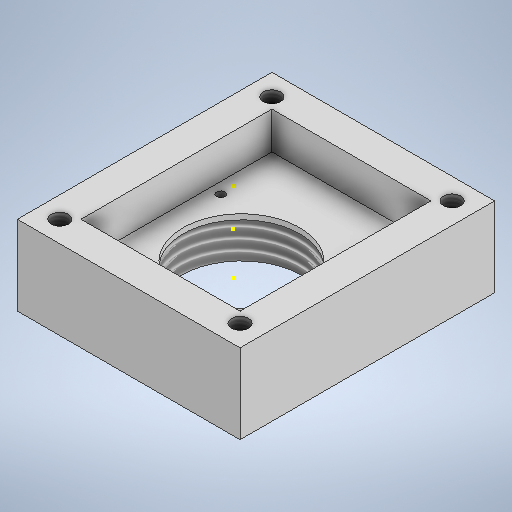
# Autodesk Inventor part: front holder
Saved by Autodesk Inventor 2025 (Build 290162010, 162A)
## iProperties
Created: 2025-05-06
Part Number: front holder
Material: Generisch
Document SubType Name: Sheet Metal
Designer: sharmalakshya
Density: 1 g/cm^3
Sheet Metal Rule: Default
Appearance: Vorgabe
Author: sharmalakshya
Autodesk Inventor part; units mm, degrees
ref_plane "YZ Plane" through (0, 0, 0) normal (1, 0, 0) x (0, 1, 0)
ref_plane "XZ Plane" through (0, 0, 0) normal (0, 1, 0) x (-1, 0, 0)
ref_plane "XY Plane" through (0, 0, 0) normal (0, 0, 1) x (1, 0, 0)
sketch "Sketch1" plane through (0, 0, 0) normal (0, 1, 0) x (-1, 0, 0)
  line L0 (14.8437, 25.7748) -> (-27.1563, 25.7748)
  line L1 (-27.1563, 25.7748) -> (-27.1563, -22.2252)
  line L2 (-27.1563, -22.2252) -> (14.8437, -22.2252)
  line L3 (14.8437, -22.2252) -> (14.8437, 25.7748)
  point P0 (0, 0)
  dimension "d0" = 48
  dimension "d1" = 42
  constraints: 8 end point, 2 parallel, 1 horizontal, 1 perpendicular
  measures "d0" distance of L2.end L0.start
  measures "d1" distance of L1.end L2.end
extrude "Extrusion1" add sketch "Sketch1" along normal blind 15
sketch "Sketch2" plane through (0, 15, 0) normal (0, 1, 0) x (1, 0, 0)
  line L0 (-8.8437, -19.7748) -> (21.1563, -19.7748)
  line L1 (21.1563, -19.7748) -> (21.1563, 16.2252)
  line L2 (21.1563, 16.2252) -> (-8.8437, 16.2252)
  line L3 (-8.8437, 16.2252) -> (-8.8437, -19.7748)
  line L4 (-14.8437, 22.2252) -> (-14.8437, -25.7748) projected
  line L5 (27.1563, 22.2252) -> (-14.8437, 22.2252) projected
  point P0 (0, 0)
  dimension "d4" = 36
  dimension "d5" = 30
  dimension "d6" = 6
  dimension "d7" = 6
  constraints: 8 end point, 2 parallel, 1 horizontal, 1 perpendicular
  measures "d4" distance of L2.end L0.start
  measures "d5" distance of L1.end L2.end
  measures "d6" distance between parallel lines of L4 L3
  measures "d7" distance between parallel lines of L5 L2
extrude "Extrusion2" cut sketch "Sketch2" against normal blind 7
sketch "Sketch4" plane through (0, 8, 0) normal (0, 1, 0) x (1, 0, 0)
  point P0 (0, 0)
sketch "Sketch6" plane through (0, 8, 0) normal (0, 1, 0) x (1, 0, 0)
  point P0 (0, 0)
sketch "Sketch7" plane through (0, 8, 0) normal (0, 1, 0) x (1, 0, 0)
  line L0 (21.1563, -19.7748) -> (-8.8437, -19.7748) projected
  line L1 (21.1563, -19.7748) -> (17.7563, -19.7748)
  line L2 (17.7563, -19.7748) -> (17.7563, -16.0248)
  line L3 (17.7563, -16.0248) -> (21.1563, -16.0248)
  line L4 (21.1563, -16.0248) -> (21.1563, -19.7748)
  line L5 (17.7563, -16.0248) -> (-6.7437, -16.0248)
  line L6 (-6.7437, -16.0248) -> (-6.7437, 4.4752)
  line L7 (-6.7437, 4.4752) -> (17.7563, 4.4752)
  line L8 (17.7563, 4.4752) -> (17.7563, -16.0248)
  point P0 (0, 0)
  dimension "d31" = 3.75
  dimension "d32" = 3.4
  dimension "d33" = 24.5
  dimension "d34" = 20.5
  constraints: 16 end point, 4 parallel, 2 horizontal, 2 perpendicular
  measures "d31" distance of L1.end L2.end
  measures "d32" distance of L2.end L3.end
  measures "d33" distance of L2.end L5.end
  measures "d34" distance of L7.end L2.end
hole "Hole3" at (17.7563, 8, 16.0248) at (-6.7437, 8, -4.4752) direction (0, -1, 0) diameter 1.567 depth 6.2992 thread size "M2x0.4" class "6H" standard "ANSI Metric M Profile"
sketch "Sketch8" plane through (0, 0, 0) normal (0, -1, 0) x (1, 0, 0)
  point P0 (0, 0)
sketch "Sketch9" plane through (0, 0, 0) normal (0, -1, 0) x (1, 0, 0)
  line L0 (-14.8437, -22.2252) -> (-14.8437, 25.7748) projected
  line L1 (-14.8437, 25.7748) -> (6.1563, 25.7748)
  line L2 (6.1563, 25.7748) -> (6.1563, 4.5248)
  line L3 (6.1563, 4.5248) -> (-14.8437, 4.5248)
  line L4 (-14.8437, 4.5248) -> (-14.8437, 25.7748)
  point P0 (0, 0)
  dimension "d42" = 21.25
  dimension "d43" = 21
  constraints: 8 end point, 2 parallel, 1 horizontal, 1 perpendicular
  measures "d42" distance of L1.end L2.end
  measures "d43" distance of L2.end L3.end
hole "Hole4" at (6.1563, 0, 4.5248) direction (0, 1, 0) diameter 22.8349 depth 7 thread size "M25x2" class "6H" standard "ANSI Metric M Profile"
sketch "Sketch10" plane through (6.1563, 7, 4.5248) normal (0, -1, 0) x (1, 0, 0)
  line L0 (-21, -26.75) -> (-21, 21.25) projected
  line L1 (-21, 21.25) -> (0, 21.25)
  line L2 (0, 21.25) -> (0, 0)
  line L3 (0, 0) -> (-21, 0)
  line L4 (-21, 0) -> (-21, 21.25)
  point P0 (-6.1563, -4.5248)
  dimension "d51" = 21.25
  dimension "d52" = 21
  constraints: 8 end point, 2 parallel, 1 horizontal, 1 perpendicular
  measures "d51" distance of L1.end L2.end
  measures "d52" distance of L2.end L3.end
hole "Hole5" at (6.1563, 7, 4.5248) direction (0, 1, 0) diameter 22 depth 61.1124
sketch "Sketch11" plane through (27.1563, 0, -22.2252) normal (0, 0, -1) x (-1, 0, 0)
  line L0 (0, 0) -> (21, 0)
  line L1 (21, 0) -> (21, 7.5)
  line L2 (21, 7.5) -> (0, 7.5)
  line L3 (0, 7.5) -> (0, 0)
  point P0 (27.1563, 0)
  dimension "d60" = 7.5
  dimension "d61" = 21
  constraints: 8 end point, 2 parallel, 1 horizontal, 1 perpendicular
  measures "d60" distance of L0.end L1.end
  measures "d61" distance of L1.end L2.end
hole "Hole6" at (6.1563, 7.5, -22.2252) direction (0, 0, 1) diameter 3.242 depth 5 thread size "M4x0.7" class "6H" standard "ANSI Metric M Profile"
sketch "Sketch12" plane through (-14.8437, 0, -22.2252) normal (-1, 0, 0) x (0, 0, 1)
  point P0 (22.2252, 0)
sketch "Sketch13" plane through (-14.8437, 0, -22.2252) normal (-1, 0, 0) x (0, 0, 1)
  line L0 (0, 15) -> (48, 15) projected
  line L1 (48, 15) -> (24, 15)
  line L2 (24, 15) -> (24, 7.5)
  line L3 (24, 7.5) -> (48, 7.5)
  line L4 (48, 7.5) -> (48, 15)
  point P0 (22.2252, 0)
  dimension "d69" = 24
  dimension "d70" = 7.5
  constraints: 8 end point, 2 parallel, 1 horizontal, 1 perpendicular
  measures "d69" distance of L2.end L3.end
  measures "d70" distance of L1.end L2.end
hole "Hole7" at (-14.8437, 7.5, 1.7748) direction (1, 0, 0) diameter 3.242 depth 5 thread size "M4x0.7" class "6H" standard "ANSI Metric M Profile"
sketch "Sketch14" plane through (0, 15, 0) normal (0, 1, 0) x (1, 0, 0)
  point P0 (0, 0)
sketch "Sketch15" plane through (0, 15, 0) normal (0, 1, 0) x (1, 0, 0)
  point P0 (0, 0)
sketch "Sketch16" plane through (0, 15, 0) normal (0, 1, 0) x (1, 0, 0)
  line L0 (23.1563, -21.7748) -> (-10.8437, -21.7748)
  line L1 (-10.8437, -21.7748) -> (-10.8437, 18.2252)
  line L2 (-10.8437, 18.2252) -> (23.1563, 18.2252)
  line L3 (23.1563, 18.2252) -> (23.1563, -21.7748)
  line L4 (-14.8437, -25.7748) -> (27.1563, -25.7748) projected
  line L5 (27.1563, -25.7748) -> (27.1563, 22.2252) projected
  point P0 (0, 0)
  dimension "d78" = 34
  dimension "d79" = 40
  dimension "d80" = 4
  dimension "d81" = 4
  constraints: 8 end point, 2 parallel, 1 horizontal, 1 perpendicular
  measures "d78" distance of L0.start L0.end
  measures "d79" distance of L0.end L1.end
  measures "d80" distance between parallel lines of L4 L0
  measures "d81" distance between parallel lines of L5 L3
hole "Hole8" at (23.1563, 15, 21.7748) at (-10.8437, 15, 21.7748) at (23.1563, 15, -18.2252) at (-10.8437, 15, -18.2252) direction (0, -1, 0) diameter 3.242 depth 11.811 thread size "M4x0.7" class "6H" standard "ANSI Metric M Profile"
equation "\"Biegeradius\" = Stärke"
equation "\"BreiteBiegungsfreistellung\" = Stärke"
equation "\"TiefeBiegungsfreistellung\" = 0.5 * Stärke"
equation "\"GrößeEckenfreistellung\" = 4 * Stärke"
equation "\"MinimalRest\" = 2 * Stärke"
equation "\"Übergangsradius\" = Biegeradius"
equation "\"JacobiRadiusGröße\" = Biegeradius"
equation "\"Abstandsgröße\" = Stärke"
equation "\"Stärke\" = 3.048"
body "Solid1"
